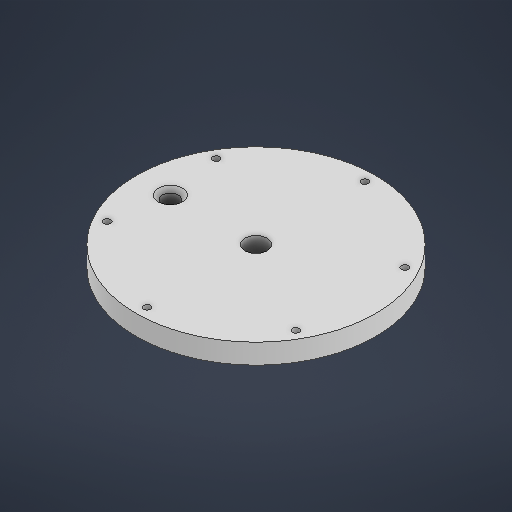
# Autodesk Inventor part: Rückwand
Saved by Autodesk Inventor 2027.1 (Build 311270010, 270A)
## iProperties
Created: 2026-10-16
Part Number: Rückwand
Material: Generic
Document SubType Name: Modeling
Designer: nicol
Density: 1 g/cm^3
Appearance: Default
Author: nicol
Autodesk Inventor part; units mm, degrees
ref_plane "YZ Plane" through (0, 0, 0) normal (1, 0, 0) x (0, 1, 0)
ref_plane "XZ Plane" through (0, 0, 0) normal (0, 1, 0) x (-1, 0, 0)
ref_plane "XY Plane" through (0, 0, 0) normal (0, 0, 1) x (1, 0, 0)
sketch "Sketch1" plane through (0, 0, 0) normal (0, 1, 0) x (-1, 0, 0)
  circle A0 centre (0, 0) radius 60
  dimension "d0" = 120
  constraints: 1 centre point, 1 coincident
  measures "d0" diameter of A0
extrude "Extrusion1" add sketch "Sketch1" along normal blind 10
sketch "Sketch2" plane through (0, 0, 0) normal (0, -1, 0) x (1, 0, 0)
  circle A0 centre (0, 0) radius 60 projected
  dimension "d10" = 0
  dimension "d11" = 0
  measures "d10" distance of A0.centre point (0, 0)
  measures "d11" distance of A0.centre point (0, 0)
hole "Hole1" at (0, 0, 0) direction (0, 1, 0) diameter 11 end through all
sketch "Sketch3" plane through (0, 0, 0) normal (0, -1, 0) x (1, 0, 0)
  point P0 (0, 0)
  point P1 (0, -54.65)
  dimension "d19" = 54.65
  dimension "d20" = 0
  measures "d19" distance of point (0, 0) point (0, -54.65)
  measures "d20" horizontal distance of point (0, -54.65) point (0, 0)
hole "Hole2" at (0, 0, -54.65) direction (0, 1, 0) diameter 3.4 end through all
pattern_circular "Circular Pattern1" count 6 over 360 about axis through (0, -10, 0) along (0, 1, 0) of "Hole2"
sketch "Sketch4" plane through (0, 0, 0) normal (0, -1, 0) x (1, 0, 0)
  point P0 (0, 0)
  point P1 (-43, 0)
  dimension "d31" = 43
  dimension "d32" = 0
  measures "d31" distance of point (0, 0) point (-43, 0)
  measures "d32" vertical distance of point (0, 0) point (-43, 0)
hole "Hole3" at (-43, 0, 0) direction (0, 1, 0) diameter 8 end through all
chamfer "Chamfer1" distance 2 angle 45 2 edges at (-43, 0, 4) (-43, 10, 4)
sketch "Sketch6" plane through (0, 0, 0) normal (0, -1, 0) x (1, 0, 0)
  point P0 (0, 0)
  point P1 (-20, 30)
  dimension "d58" = 20
  dimension "d59" = 30
  measures "d58" horizontal distance of point (0, 0) point (-20, 30)
  measures "d59" vertical distance of point (0, 0) point (-20, 30)
hole "Hole5" at (-20, 0, 30) direction (0, 1, 0) diameter 4.134 depth 7.5 tip angle 118 thread size "M5x0.8" class "6H" standard "ISO Metric profile"
pattern_linear "Rectangular Pattern2" count 2 spacing 40 along (1, 0, 0) count 2 spacing 60 along (0, 0, -1) of "Hole5"
body "Solid1"
